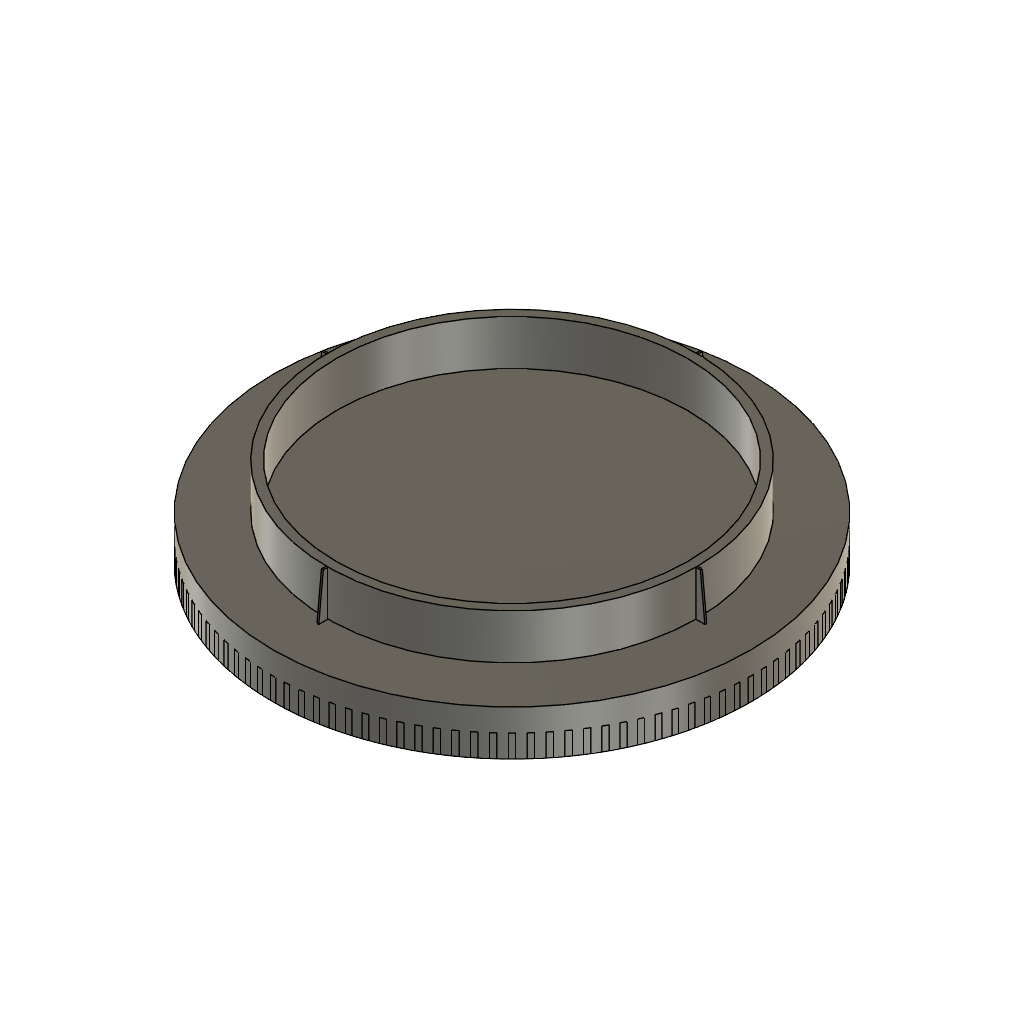
42mm_Cap (Autodesk Fusion 360 design; units mm, degrees)
part number: 2026-09-11-16-52-09-316
Autodesk Fusion 360 part; units mm, degrees
sketch "スケッチ1" plane through (0, 0, 0) normal (0, 0, 1) x (1, 0, 0)
  circle A0 centre (0, 0) radius 26.5
  dimension "d1" = 53
  constraint coincident A0.centre origin
  measures "d1" diameter of A0
extrude "押し出し1" add sketch "スケッチ1" along normal blind 5 makes body 1
sketch "スケッチ2" plane through (0, 0, 5) normal (0, 0, 1) x (-1, 0, 0)
  circle A0 centre (0, 0) radius 26.5
  circle A1 centre (0, 0) radius 20.5
  dimension "d4" = 41
  constraint concentric A0 A1
  measures "d4" diameter of A1
extrude "押し出し2" add sketch "スケッチ2" along normal blind 5 contours A1 bodies 1
hole "穴1" at (0, 0, 10) direction (0, 0, -1) diameter 39 depth 5 tip angle 180 bodies 1
sketch "スケッチ3" plane through (0, 0, 5) normal (0, 0, 1) x (-1, 0, 0)
  circle A0 centre (0, 0) radius 20.5
  circle A1 centre (0, 0) radius 26.5
  line L0 (27, 0.1) -> (28, 0.1)
  line L1 (28, 0.1) -> (28, -0.1)
  line L2 (28, -0.1) -> (27, -0.1)
  line L3 (27, -0.1) -> (27, 0.1)
  constraint horizontal L0
  constraint vertical L1
  constraint horizontal L2
  constraint vertical L3
sketch "スケッチ4" plane through (0, -0.1, 0) normal (0, -1, 0) x (1, 0, 0)
  line L0 (-28, 5) -> (-27, 5)
  line L1 (-27, 5) -> (-27, 10)
  line L2 (-27, 10) -> (-28, 10)
  line L3 (-28, 10) -> (-28, 5)
  line L4 (-28.5, 10) -> (-28.5, 5)
  line L5 (-28.5, 5) -> (-29.5, 5)
  line L6 (-29.5, 5) -> (-29, 10)
  line L7 (-29, 10) -> (-28.5, 10)
  constraint vertical L4
  constraint perpendicular L4 L5
  constraint perpendicular L4 L7
extrude "押し出し4" add sketch "スケッチ4" against normal blind 0.2 separate body contours L4 L5 L6 L7 makes body 2
copy_body "ボディのコピーと貼り付け1" bodies 2 makes body 3
move_body "移動1" bodies 3 to x (1, 0, 0) y (0, 1, 0) z (0, 0, 1) at (1.4, 0, 0)
copy_body "ボディのコピーと貼り付け2" bodies 3 2 makes body 4 makes body 5
move_body "移動2" bodies 4 5 to x (1, 0, 0) y (0, 1, 0) z (0, 0, 1) at (-2.7861, 0, 0.2786)
move_body "移動4" bodies 3 to x (1, 0, 0) y (0, 1, 0) z (0, 0, 1) at (6.6, 0, 0)
move_body "移動5" bodies 2 to x (-1, 0, 0) y (0, -1, 0) z (0, 0, 1) at (-8, 0, 0)
move_body "移動7" bodies 5 to x (0, -1, 0) y (1, 0, 0) z (0, 0, 1) at (0.0139, -10.7861, 0)
move_body "移動8" bodies 4 to x (0, 1, 0) y (-1, 0, 0) z (0, 0, 1) at (-0.0361, 9.4361, 0)
hole "穴2" at (0, 0, 0) direction (0, 0, 1) diameter 48 depth 3 tip angle 180 bodies 1
sketch "スケッチ5" plane through (0, 0, 0) normal (0, 0, 1) x (1, 0, 0)
  line L0 (26.1984, -0.294) -> (26.4983, -0.2973)
  line L1 (26.4983, -0.2973) -> (26.4983, 0.2973)
  line L2 (26.4983, 0.2973) -> (26.1984, 0.294)
  line L3 (26.1984, 0.294) -> (26.1984, -0.294)
extrude "押し出し5" cut sketch "スケッチ5" along normal blind 0 and the other way blind 5 from surface at 2.5 bodies 1
pattern_circular "C パターン1" count 112 over 360 about axis through (0, 0, 1.75) along (0, 0, 1) of "押し出し5"
move_body "移動9" bodies 5 to x (1, 0, 0) y (0, 1, 0) z (0, 0, 1) at (0, 0, -0.3)
move_body "移動10" bodies 4 to x (1, 0, 0) y (0, 1, 0) z (0, 0, 1) at (0, -0.05, -0.3)
